210104_P01_WALL-PANEL-ASSY-SIDE-UPPER-RH_CAD (Autodesk Fusion 360 design; units mm, degrees)
description: WALL - PANEL ASSY - SIDE UPPER - RH | Vách phải - cụm tấm trên | P01 | position R2
part number: 210104
description: WALL - PANEL FRAME - SIDE UPPER - RH | Vách phải - khung trên | P01
part number: 211104
description: WALL - SKIN - SIDE UPPER - RH | Vách phải - tấm ốp alu trên | P01
part number: 211304
description: WALL - CAVITY FILL - SIDE UPPER - RH | Vách phải - bông PET trên | P01
part number: 211504
description: HARDWARE - STOP WASHER - Ø10.5 X Ø20 X 1.5 - AL | Long đen chặn nhôm | P01
part number: 831002
description: HARDWARE - RIVET NUT - M6 - SHEREX CAH3-610-4.2 | Tán rút M6 | P01
part number: 838003
Autodesk Fusion 360 part; units mm, degrees
(part 1 of 2)
ref_plane "WorkPlane1" through (0, 0, 1257.26) normal (0, 0, 1) x (1, 0, 0) in component "211104 WALL - PANEL FRAME - SIDE UPPER - RH"
sketch "SKETCH - RAIL - BOTTOM TUBE" plane through (0, 0, 1257.26) normal (0, 0, 1) x (1, 0, 0) in component "211104 WALL - PANEL FRAME - SIDE UPPER - RH"
  line L0 (1204, -642.74) -> (1244, -642.74)
  line L1 (1244, -642.74) -> (1244, 847)
  line L2 (1244, 847) -> (1204, 847)
  line L3 (1204, 847) -> (1204, -642.74)
  dimension "d167" = 40
  dimension "d168" = 1489.74
  dimension "d169" = 1204
  dimension "d170" = 642.74
  constraint horizontal L0
  constraint vertical L1
  constraint horizontal L2
  constraint vertical L3
  measures "d167" horizontal distance of L0.start L0.end
  measures "d168" vertical distance of L0.start L2.end
  measures "d169" horizontal distance of origin L0.start
  measures "d170" vertical distance of origin L0.start
extrude "EXTRUDE - RAIL - BOTTOM TUBE" add sketch "SKETCH - RAIL - BOTTOM TUBE" along normal blind 20 makes body 1 in component "211104 WALL - PANEL FRAME - SIDE UPPER - RH"
ref_plane "WorkPlane2" through (0, 0, 1258.46) normal (0, 0, 1) x (1, 0, 0) in component "211104 WALL - PANEL FRAME - SIDE UPPER - RH"
sketch "SKETCH - RAIL - BOTTOM BORE" plane through (0, 0, 1258.46) normal (0, 0, 1) x (1, 0, 0) in component "211104 WALL - PANEL FRAME - SIDE UPPER - RH"
  line L0 (1205.2, -642.74) -> (1242.8, -642.74)
  line L1 (1242.8, -642.74) -> (1242.8, 847)
  line L2 (1242.8, 847) -> (1205.2, 847)
  line L3 (1205.2, 847) -> (1205.2, -642.74)
  dimension "d175" = 37.6
  dimension "d176" = 1489.74
  dimension "d177" = 1205.2
  dimension "d178" = 642.74
  constraint horizontal L0
  constraint vertical L1
  constraint horizontal L2
  constraint vertical L3
  measures "d175" horizontal distance of L0.start L0.end
  measures "d176" vertical distance of L0.start L2.end
  measures "d177" horizontal distance of origin L0.start
  measures "d178" vertical distance of origin L0.start
extrude "CUT - RAIL - BOTTOM BORE" cut sketch "SKETCH - RAIL - BOTTOM BORE" along normal blind 17.6 bodies 1 in component "211104 WALL - PANEL FRAME - SIDE UPPER - RH"
ref_plane "WorkPlane3" through (0, 0, 2360) normal (0, 0, 1) x (1, 0, 0) in component "211104 WALL - PANEL FRAME - SIDE UPPER - RH"
sketch "SKETCH - RAIL - TOP TUBE" plane through (0, 0, 2360) normal (0, 0, 1) x (1, 0, 0) in component "211104 WALL - PANEL FRAME - SIDE UPPER - RH"
  line L0 (1204, -642.74) -> (1244, -642.74)
  line L1 (1244, -642.74) -> (1244, 847)
  line L2 (1244, 847) -> (1204, 847)
  line L3 (1204, 847) -> (1204, -642.74)
  dimension "d183" = 40
  dimension "d184" = 1489.74
  dimension "d185" = 1204
  dimension "d186" = 642.74
  constraint horizontal L0
  constraint vertical L1
  constraint horizontal L2
  constraint vertical L3
  measures "d183" horizontal distance of L0.start L0.end
  measures "d184" vertical distance of L0.start L2.end
  measures "d185" horizontal distance of origin L0.start
  measures "d186" vertical distance of origin L0.start
extrude "EXTRUDE - RAIL - TOP TUBE" add sketch "SKETCH - RAIL - TOP TUBE" along normal blind 40 separate body makes body 2 in component "211104 WALL - PANEL FRAME - SIDE UPPER - RH"
ref_plane "WorkPlane4" through (0, 0, 2361.2) normal (0, 0, 1) x (1, 0, 0) in component "211104 WALL - PANEL FRAME - SIDE UPPER - RH"
sketch "SKETCH - RAIL - TOP BORE" plane through (0, 0, 2361.2) normal (0, 0, 1) x (1, 0, 0) in component "211104 WALL - PANEL FRAME - SIDE UPPER - RH"
  line L0 (1205.2, -642.74) -> (1242.8, -642.74)
  line L1 (1242.8, -642.74) -> (1242.8, 847)
  line L2 (1242.8, 847) -> (1205.2, 847)
  line L3 (1205.2, 847) -> (1205.2, -642.74)
  dimension "d191" = 37.6
  dimension "d192" = 1489.74
  dimension "d193" = 1205.2
  dimension "d194" = 642.74
  constraint horizontal L0
  constraint vertical L1
  constraint horizontal L2
  constraint vertical L3
  measures "d191" horizontal distance of L0.start L0.end
  measures "d192" vertical distance of L0.start L2.end
  measures "d193" horizontal distance of origin L0.start
  measures "d194" vertical distance of origin L0.start
extrude "CUT - RAIL - TOP BORE" cut sketch "SKETCH - RAIL - TOP BORE" along normal blind 37.6 bodies 2 in component "211104 WALL - PANEL FRAME - SIDE UPPER - RH"
ref_plane "WorkPlane5" through (0, 0, 1277.26) normal (0, 0, 1) x (1, 0, 0) in component "211104 WALL - PANEL FRAME - SIDE UPPER - RH"
sketch "SKETCH - STILE - FRONT TUBE" plane through (0, 0, 1277.26) normal (0, 0, 1) x (1, 0, 0) in component "211104 WALL - PANEL FRAME - SIDE UPPER - RH"
  line L0 (1204, -642.74) -> (1244, -642.74)
  line L1 (1244, -642.74) -> (1244, -622.74)
  line L2 (1244, -622.74) -> (1204, -622.74)
  line L3 (1204, -622.74) -> (1204, -642.74)
  dimension "d199" = 40
  dimension "d200" = 20
  dimension "d201" = 1204
  dimension "d202" = 642.74
  constraint horizontal L0
  constraint vertical L1
  constraint horizontal L2
  constraint vertical L3
  measures "d199" horizontal distance of L0.start L0.end
  measures "d200" vertical distance of L0.start L2.end
  measures "d201" horizontal distance of origin L0.start
  measures "d202" vertical distance of origin L0.start
extrude "EXTRUDE - STILE - FRONT TUBE" add sketch "SKETCH - STILE - FRONT TUBE" along normal blind 1082.74 separate body makes body 3 in component "211104 WALL - PANEL FRAME - SIDE UPPER - RH"
ref_plane "WorkPlane6" through (0, 0, 1277.26) normal (0, 0, 1) x (1, 0, 0) in component "211104 WALL - PANEL FRAME - SIDE UPPER - RH"
sketch "SKETCH - STILE - FRONT BORE" plane through (0, 0, 1277.26) normal (0, 0, 1) x (1, 0, 0) in component "211104 WALL - PANEL FRAME - SIDE UPPER - RH"
  line L0 (1205.2, -641.54) -> (1242.8, -641.54)
  line L1 (1242.8, -641.54) -> (1242.8, -623.94)
  line L2 (1242.8, -623.94) -> (1205.2, -623.94)
  line L3 (1205.2, -623.94) -> (1205.2, -641.54)
  dimension "d207" = 37.6
  dimension "d208" = 17.6
  dimension "d209" = 1205.2
  dimension "d210" = 641.54
  constraint horizontal L0
  constraint vertical L1
  constraint horizontal L2
  constraint vertical L3
  measures "d207" horizontal distance of L0.start L0.end
  measures "d208" vertical distance of L0.start L2.end
  measures "d209" horizontal distance of origin L0.start
  measures "d210" vertical distance of origin L0.start
extrude "CUT - STILE - FRONT BORE" cut sketch "SKETCH - STILE - FRONT BORE" along normal blind 1082.74 bodies 3 in component "211104 WALL - PANEL FRAME - SIDE UPPER - RH"
ref_plane "WorkPlane7" through (0, 0, 1277.26) normal (0, 0, 1) x (1, 0, 0) in component "211104 WALL - PANEL FRAME - SIDE UPPER - RH"
sketch "SKETCH - STILE - BACK TUBE" plane through (0, 0, 1277.26) normal (0, 0, 1) x (1, 0, 0) in component "211104 WALL - PANEL FRAME - SIDE UPPER - RH"
  line L0 (1204, 807) -> (1244, 807)
  line L1 (1244, 807) -> (1244, 847)
  line L2 (1244, 847) -> (1204, 847)
  line L3 (1204, 847) -> (1204, 807)
  dimension "d215" = 40
  dimension "d216" = 40
  dimension "d217" = 1204
  dimension "d218" = 807
  constraint horizontal L0
  constraint vertical L1
  constraint horizontal L2
  constraint vertical L3
  measures "d215" horizontal distance of L0.start L0.end
  measures "d216" vertical distance of L0.start L2.end
  measures "d217" horizontal distance of origin L0.start
  measures "d218" vertical distance of origin L0.start
extrude "EXTRUDE - STILE - BACK TUBE" add sketch "SKETCH - STILE - BACK TUBE" along normal blind 1082.74 separate body makes body 4 in component "211104 WALL - PANEL FRAME - SIDE UPPER - RH"
ref_plane "WorkPlane8" through (0, 0, 1277.26) normal (0, 0, 1) x (1, 0, 0) in component "211104 WALL - PANEL FRAME - SIDE UPPER - RH"
sketch "SKETCH - STILE - BACK BORE" plane through (0, 0, 1277.26) normal (0, 0, 1) x (1, 0, 0) in component "211104 WALL - PANEL FRAME - SIDE UPPER - RH"
  line L0 (1205.2, 808.2) -> (1242.8, 808.2)
  line L1 (1242.8, 808.2) -> (1242.8, 845.8)
  line L2 (1242.8, 845.8) -> (1205.2, 845.8)
  line L3 (1205.2, 845.8) -> (1205.2, 808.2)
  dimension "d223" = 37.6
  dimension "d224" = 37.6
  dimension "d225" = 1205.2
  dimension "d226" = 808.2
  constraint horizontal L0
  constraint vertical L1
  constraint horizontal L2
  constraint vertical L3
  measures "d223" horizontal distance of L0.start L0.end
  measures "d224" vertical distance of L0.start L2.end
  measures "d225" horizontal distance of origin L0.start
  measures "d226" vertical distance of origin L0.start
extrude "CUT - STILE - BACK BORE" cut sketch "SKETCH - STILE - BACK BORE" along normal blind 1082.74 bodies 4 in component "211104 WALL - PANEL FRAME - SIDE UPPER - RH"
ref_plane "WorkPlane9" through (0, 0, 1277.26) normal (0, 0, 1) x (1, 0, 0) in component "211104 WALL - PANEL FRAME - SIDE UPPER - RH"
sketch "SKETCH - STILE - MID 1 TUBE" plane through (0, 0, 1277.26) normal (0, 0, 1) x (1, 0, 0) in component "211104 WALL - PANEL FRAME - SIDE UPPER - RH"
  line L0 (1204, -277.805) -> (1244, -277.805)
  line L1 (1244, -277.805) -> (1244, -257.805)
  line L2 (1244, -257.805) -> (1204, -257.805)
  line L3 (1204, -257.805) -> (1204, -277.805)
  dimension "d231" = 40
  dimension "d232" = 20
  dimension "d233" = 1204
  dimension "d234" = 277.805
  constraint horizontal L0
  constraint vertical L1
  constraint horizontal L2
  constraint vertical L3
  measures "d231" horizontal distance of L0.start L0.end
  measures "d232" vertical distance of L0.start L2.end
  measures "d233" horizontal distance of origin L0.start
  measures "d234" vertical distance of origin L0.start
extrude "EXTRUDE - STILE - MID 1 TUBE" add sketch "SKETCH - STILE - MID 1 TUBE" along normal blind 1082.74 separate body makes body 5 in component "211104 WALL - PANEL FRAME - SIDE UPPER - RH"
ref_plane "WorkPlane10" through (0, 0, 1277.26) normal (0, 0, 1) x (1, 0, 0) in component "211104 WALL - PANEL FRAME - SIDE UPPER - RH"
sketch "SKETCH - STILE - MID 1 BORE" plane through (0, 0, 1277.26) normal (0, 0, 1) x (1, 0, 0) in component "211104 WALL - PANEL FRAME - SIDE UPPER - RH"
  line L0 (1205, -276.805) -> (1243, -276.805)
  line L1 (1243, -276.805) -> (1243, -258.805)
  line L2 (1243, -258.805) -> (1205, -258.805)
  line L3 (1205, -258.805) -> (1205, -276.805)
  dimension "d239" = 38
  dimension "d240" = 18
  dimension "d241" = 1205
  dimension "d242" = 276.805
  constraint horizontal L0
  constraint vertical L1
  constraint horizontal L2
  constraint vertical L3
  measures "d239" horizontal distance of L0.start L0.end
  measures "d240" vertical distance of L0.start L2.end
  measures "d241" horizontal distance of origin L0.start
  measures "d242" vertical distance of origin L0.start
extrude "CUT - STILE - MID 1 BORE" cut sketch "SKETCH - STILE - MID 1 BORE" along normal blind 1082.74 bodies 5 in component "211104 WALL - PANEL FRAME - SIDE UPPER - RH"
pattern_linear "PATTERN - STILES - MID" count 3 spacing 364.935 along (0, 1, 0) of bodies 5 makes body 6 at (1230.6667, 107.13, 1999.0867) makes body 7 at (1230.6667, 472.065, 1999.0867) in component "211104 WALL - PANEL FRAME - SIDE UPPER - RH"
ref_plane "WorkPlane1" through (0, 0, 1257.26) normal (0, 0, 1) x (1, 0, 0) in component "211304 WALL - SKIN - SIDE UPPER - RH"
sketch "SKETCH - SKIN PLATE" plane through (0, 0, 1257.26) normal (0, 0, 1) x (1, 0, 0) in component "211304 WALL - SKIN - SIDE UPPER - RH"
  line L0 (1247, -642.74) -> (1250, -642.74)
  line L1 (1250, -642.74) -> (1250, 850)
  line L2 (1250, 850) -> (1247, 850)
  line L3 (1247, 850) -> (1247, -642.74)
  dimension "d251" = 3
  dimension "d252" = 1492.74
  dimension "d253" = 1247
  dimension "d254" = 642.74
  constraint horizontal L0
  constraint vertical L1
  constraint horizontal L2
  constraint vertical L3
  measures "d251" horizontal distance of L0.start L0.end
  measures "d252" vertical distance of L0.start L2.end
  measures "d253" horizontal distance of origin L0.start
  measures "d254" vertical distance of origin L0.start
extrude "EXTRUDE - SKIN PLATE" add sketch "SKETCH - SKIN PLATE" along normal blind 1142.74 separate body makes body 8 in component "211304 WALL - SKIN - SIDE UPPER - RH"
ref_plane "WorkPlane2" through (0, 0, 1257.26) normal (0, 0, 1) x (1, 0, 0) in component "211304 WALL - SKIN - SIDE UPPER - RH"
sketch "SKETCH - SKIN BACK RETURN" plane through (0, 0, 1257.26) normal (0, 0, 1) x (1, 0, 0) in component "211304 WALL - SKIN - SIDE UPPER - RH"
  line L0 (1204, 847) -> (1247, 847)
  line L1 (1247, 847) -> (1247, 850)
  line L2 (1247, 850) -> (1204, 850)
  line L3 (1204, 850) -> (1204, 847)
  dimension "d259" = 43
  dimension "d260" = 3
  dimension "d261" = 1204
  dimension "d262" = 847
  constraint horizontal L0
  constraint vertical L1
  constraint horizontal L2
  constraint vertical L3
  measures "d259" horizontal distance of L0.start L0.end
  measures "d260" vertical distance of L0.start L2.end
  measures "d261" horizontal distance of origin L0.start
  measures "d262" vertical distance of origin L0.start
extrude "JOIN - SKIN BACK RETURN" add sketch "SKETCH - SKIN BACK RETURN" along normal blind 1142.74 bodies 8 in component "211304 WALL - SKIN - SIDE UPPER - RH"
ref_plane "WorkPlane1" through (0, 0, 1277.26) normal (0, 0, 1) x (1, 0, 0) in component "211504 WALL - CAVITY FILL - SIDE UPPER - RH"
sketch "SKETCH - FILL BAY 1" plane through (0, 0, 1277.26) normal (0, 0, 1) x (1, 0, 0) in component "211504 WALL - CAVITY FILL - SIDE UPPER - RH"
  line L0 (1204, -622.74) -> (1244, -622.74)
  line L1 (1244, -622.74) -> (1244, -277.805)
  line L2 (1244, -277.805) -> (1204, -277.805)
  line L3 (1204, -277.805) -> (1204, -622.74)
  dimension "d267" = 40
  dimension "d268" = 344.935
  dimension "d269" = 1204
  dimension "d270" = 622.74
  constraint horizontal L0
  constraint vertical L1
  constraint horizontal L2
  constraint vertical L3
  measures "d267" horizontal distance of L0.start L0.end
  measures "d268" vertical distance of L0.start L2.end
  measures "d269" horizontal distance of origin L0.start
  measures "d270" vertical distance of origin L0.start
extrude "EXTRUDE - FILL BAY 1" add sketch "SKETCH - FILL BAY 1" along normal blind 1082.74 separate body makes body 9 in component "211504 WALL - CAVITY FILL - SIDE UPPER - RH"
pattern_linear "PATTERN - FILL BAYS" count 3 spacing 364.935 along (0, 1, 0) of bodies 9 makes body 10 at (1204, -27.8483, 1999.0867) makes body 11 at (1204, 337.0867, 1999.0867) in component "211504 WALL - CAVITY FILL - SIDE UPPER - RH"
ref_plane "WorkPlane2" through (0, 0, 1277.26) normal (0, 0, 1) x (1, 0, 0) in component "211504 WALL - CAVITY FILL - SIDE UPPER - RH"
sketch "SKETCH - FILL BAY LAST" plane through (0, 0, 1277.26) normal (0, 0, 1) x (1, 0, 0) in component "211504 WALL - CAVITY FILL - SIDE UPPER - RH"
  line L0 (1204, 472.065) -> (1244, 472.065)
  line L1 (1244, 472.065) -> (1244, 807)
  line L2 (1244, 807) -> (1204, 807)
  line L3 (1204, 807) -> (1204, 472.065)
  dimension "d279" = 40
  dimension "d280" = 334.935
  dimension "d281" = 1204
  dimension "d282" = 472.065
  constraint horizontal L0
  constraint vertical L1
  constraint horizontal L2
  constraint vertical L3
  measures "d279" horizontal distance of L0.start L0.end
  measures "d280" vertical distance of L0.start L2.end
  measures "d281" horizontal distance of origin L0.start
  measures "d282" vertical distance of origin L0.start
extrude "EXTRUDE - FILL BAY LAST" add sketch "SKETCH - FILL BAY LAST" along normal blind 1082.74 separate body makes body 12 in component "211504 WALL - CAVITY FILL - SIDE UPPER - RH"
ref_plane "WorkPlane3" through (0, 0, 1277.26) normal (0, 0, 1) x (1, 0, 0) in component "211504 WALL - CAVITY FILL - SIDE UPPER - RH"
sketch "SKETCH - FILL POCKET BOTTOM BOLT 1" plane through (0, 0, 1277.26) normal (0, 0, 1) x (1, 0, 0) in component "211504 WALL - CAVITY FILL - SIDE UPPER - RH"
  line L0 (1204, -452.74) -> (1244, -452.74)
  line L1 (1244, -452.74) -> (1244, -392.74)
  line L2 (1244, -392.74) -> (1204, -392.74)
  line L3 (1204, -392.74) -> (1204, -452.74)
  dimension "d287" = 40
  dimension "d288" = 60
  dimension "d289" = 1204
  dimension "d290" = 452.74
  constraint horizontal L0
  constraint vertical L1
  constraint horizontal L2
  constraint vertical L3
  measures "d287" horizontal distance of L0.start L0.end
  measures "d288" vertical distance of L0.start L2.end
  measures "d289" horizontal distance of origin L0.start
  measures "d290" vertical distance of origin L0.start
extrude "CUT - FILL POCKET BOTTOM BOLT 1" cut sketch "SKETCH - FILL POCKET BOTTOM BOLT 1" along normal blind 60 bodies 9 in component "211504 WALL - CAVITY FILL - SIDE UPPER - RH"
ref_plane "WorkPlane4" through (0, 0, 1277.26) normal (0, 0, 1) x (1, 0, 0) in component "211504 WALL - CAVITY FILL - SIDE UPPER - RH"
sketch "SKETCH - FILL POCKET BOTTOM BOLT 2" plane through (0, 0, 1277.26) normal (0, 0, 1) x (1, 0, 0) in component "211504 WALL - CAVITY FILL - SIDE UPPER - RH"
  line L0 (1204, -101.8267) -> (1244, -101.8267)
  line L1 (1244, -101.8267) -> (1244, -41.8267)
  line L2 (1244, -41.8267) -> (1204, -41.8267)
  line L3 (1204, -41.8267) -> (1204, -101.8267)
  dimension "d295" = 40
  dimension "d296" = 60
  dimension "d297" = 1204
  dimension "d298" = 101.8267
  constraint horizontal L0
  constraint vertical L1
  constraint horizontal L2
  constraint vertical L3
  measures "d295" horizontal distance of L0.start L0.end
  measures "d296" vertical distance of L0.start L2.end
  measures "d297" horizontal distance of origin L0.start
  measures "d298" vertical distance of origin L0.start
extrude "CUT - FILL POCKET BOTTOM BOLT 2" cut sketch "SKETCH - FILL POCKET BOTTOM BOLT 2" along normal blind 60 bodies 10 in component "211504 WALL - CAVITY FILL - SIDE UPPER - RH"
ref_plane "WorkPlane5" through (0, 0, 1277.26) normal (0, 0, 1) x (1, 0, 0) in component "211504 WALL - CAVITY FILL - SIDE UPPER - RH"
sketch "SKETCH - FILL POCKET BOTTOM BOLT 3" plane through (0, 0, 1277.26) normal (0, 0, 1) x (1, 0, 0) in component "211504 WALL - CAVITY FILL - SIDE UPPER - RH"
  line L0 (1204, 249.0867) -> (1244, 249.0867)
  line L1 (1244, 249.0867) -> (1244, 309.0867)
  line L2 (1244, 309.0867) -> (1204, 309.0867)
  line L3 (1204, 309.0867) -> (1204, 249.0867)
  dimension "d303" = 40
  dimension "d304" = 60
  dimension "d305" = 1204
  dimension "d306" = 249.0867
  constraint horizontal L0
  constraint vertical L1
  constraint horizontal L2
  constraint vertical L3
  measures "d303" horizontal distance of L0.start L0.end
  measures "d304" vertical distance of L0.start L2.end
  measures "d305" horizontal distance of origin L0.start
  measures "d306" vertical distance of origin L0.start
extrude "CUT - FILL POCKET BOTTOM BOLT 3" cut sketch "SKETCH - FILL POCKET BOTTOM BOLT 3" along normal blind 60 bodies 11 in component "211504 WALL - CAVITY FILL - SIDE UPPER - RH"
ref_plane "WorkPlane6" through (0, 0, 1277.26) normal (0, 0, 1) x (1, 0, 0) in component "211504 WALL - CAVITY FILL - SIDE UPPER - RH"
sketch "SKETCH - FILL POCKET BOTTOM BOLT 4" plane through (0, 0, 1277.26) normal (0, 0, 1) x (1, 0, 0) in component "211504 WALL - CAVITY FILL - SIDE UPPER - RH"
  line L0 (1204, 600) -> (1244, 600)
  line L1 (1244, 600) -> (1244, 660)
  line L2 (1244, 660) -> (1204, 660)
  line L3 (1204, 660) -> (1204, 600)
  dimension "d311" = 40
  dimension "d312" = 60
  dimension "d313" = 1204
  dimension "d314" = 600
  constraint horizontal L0
  constraint vertical L1
  constraint horizontal L2
  constraint vertical L3
  measures "d311" horizontal distance of L0.start L0.end
  measures "d312" vertical distance of L0.start L2.end
  measures "d313" horizontal distance of origin L0.start
  measures "d314" vertical distance of origin L0.start
extrude "CUT - FILL POCKET BOTTOM BOLT 4" cut sketch "SKETCH - FILL POCKET BOTTOM BOLT 4" along normal blind 60 bodies 12 in component "211504 WALL - CAVITY FILL - SIDE UPPER - RH"
ref_plane "WorkPlane7" through (0, 0, 1447.26) normal (0, 0, 1) x (1, 0, 0) in component "211504 WALL - CAVITY FILL - SIDE UPPER - RH"
sketch "SKETCH - FILL POCKET DECOR BOLT 1" plane through (0, 0, 1447.26) normal (0, 0, 1) x (1, 0, 0) in component "211504 WALL - CAVITY FILL - SIDE UPPER - RH"
  line L0 (1204, -622.74) -> (1244, -622.74)
  line L1 (1244, -622.74) -> (1244, -562.74)
  line L2 (1244, -562.74) -> (1204, -562.74)
  line L3 (1204, -562.74) -> (1204, -622.74)
  dimension "d319" = 40
  dimension "d320" = 60
  dimension "d321" = 1204
  dimension "d322" = 622.74
  constraint horizontal L0
  constraint vertical L1
  constraint horizontal L2
  constraint vertical L3
  measures "d319" horizontal distance of L0.start L0.end
  measures "d320" vertical distance of L0.start L2.end
  measures "d321" horizontal distance of origin L0.start
  measures "d322" vertical distance of origin L0.start
extrude "CUT - FILL POCKET DECOR BOLT 1" cut sketch "SKETCH - FILL POCKET DECOR BOLT 1" along normal blind 60 bodies 9 in component "211504 WALL - CAVITY FILL - SIDE UPPER - RH"
ref_plane "WorkPlane8" through (0, 0, 1798.63) normal (0, 0, 1) x (1, 0, 0) in component "211504 WALL - CAVITY FILL - SIDE UPPER - RH"
sketch "SKETCH - FILL POCKET DECOR BOLT 2" plane through (0, 0, 1798.63) normal (0, 0, 1) x (1, 0, 0) in component "211504 WALL - CAVITY FILL - SIDE UPPER - RH"
  line L0 (1204, -622.74) -> (1244, -622.74)
  line L1 (1244, -622.74) -> (1244, -562.74)
  line L2 (1244, -562.74) -> (1204, -562.74)
  line L3 (1204, -562.74) -> (1204, -622.74)
  dimension "d327" = 40
  dimension "d328" = 60
  dimension "d329" = 1204
  dimension "d330" = 622.74
  constraint horizontal L0
  constraint vertical L1
  constraint horizontal L2
  constraint vertical L3
  measures "d327" horizontal distance of L0.start L0.end
  measures "d328" vertical distance of L0.start L2.end
  measures "d329" horizontal distance of origin L0.start
  measures "d330" vertical distance of origin L0.start
extrude "CUT - FILL POCKET DECOR BOLT 2" cut sketch "SKETCH - FILL POCKET DECOR BOLT 2" along normal blind 60 bodies 9 in component "211504 WALL - CAVITY FILL - SIDE UPPER - RH"
ref_plane "WorkPlane9" through (0, 0, 2150) normal (0, 0, 1) x (1, 0, 0) in component "211504 WALL - CAVITY FILL - SIDE UPPER - RH"
sketch "SKETCH - FILL POCKET DECOR BOLT 3" plane through (0, 0, 2150) normal (0, 0, 1) x (1, 0, 0) in component "211504 WALL - CAVITY FILL - SIDE UPPER - RH"
  line L0 (1204, -622.74) -> (1244, -622.74)
  line L1 (1244, -622.74) -> (1244, -562.74)
  line L2 (1244, -562.74) -> (1204, -562.74)
  line L3 (1204, -562.74) -> (1204, -622.74)
  dimension "d335" = 40
  dimension "d336" = 60
  dimension "d337" = 1204
  dimension "d338" = 622.74
  constraint horizontal L0
  constraint vertical L1
  constraint horizontal L2
  constraint vertical L3
  measures "d335" horizontal distance of L0.start L0.end
  measures "d336" vertical distance of L0.start L2.end
  measures "d337" horizontal distance of origin L0.start
  measures "d338" vertical distance of origin L0.start
extrude "CUT - FILL POCKET DECOR BOLT 3" cut sketch "SKETCH - FILL POCKET DECOR BOLT 3" along normal blind 60 bodies 9 in component "211504 WALL - CAVITY FILL - SIDE UPPER - RH"
ref_plane "WorkPlane11" through (0, 0, 1257.26) normal (0, 0, 1) x (1, 0, 0) in component "211104 WALL - PANEL FRAME - SIDE UPPER - RH"
sketch "HOLE CENTRE - BOTTOM RAIL BOLT CLEARANCE 1" plane through (0, 0, 1257.26) normal (0, 0, 1) x (1, 0, 0) in component "211104 WALL - PANEL FRAME - SIDE UPPER - RH"
  point P0 (1224, -422.74)
  dimension "d343" = 1224
  dimension "d344" = 422.74
  measures "d343" horizontal distance of origin P0
  measures "d344" vertical distance of origin P0
hole "HOLE - BOTTOM RAIL BOLT CLEARANCE 1" at (1224, -422.74, 1257.26) direction (0, 0, 1) diameter 7 depth 1.2 tip angle 118 bodies 1 in component "211104 WALL - PANEL FRAME - SIDE UPPER - RH"
ref_plane "WorkPlane12" through (0, 0, 1277.26) normal (0, 0, 1) x (1, 0, 0) in component "211104 WALL - PANEL FRAME - SIDE UPPER - RH"
sketch "HOLE CENTRE - BOTTOM RAIL KEY ACCESS 1" plane through (0, 0, 1277.26) normal (0, 0, 1) x (1, 0, 0) in component "211104 WALL - PANEL FRAME - SIDE UPPER - RH"
  point P0 (1224, -422.74)
  dimension "d350" = 1224
  dimension "d351" = 422.74
  measures "d350" horizontal distance of origin P0
  measures "d351" vertical distance of origin P0
hole "HOLE - BOTTOM RAIL KEY ACCESS 1" at (1224, -422.74, 1277.26) direction (0, 0, -1) diameter 19 depth 1.2 tip angle 118 bodies 1 in component "211104 WALL - PANEL FRAME - SIDE UPPER - RH"
pattern_linear "PATTERN - BOTTOM RAIL BOLT HOLES" count 4 spacing 350.9133 along (0, 1, 0) of "HOLE - BOTTOM RAIL BOLT CLEARANCE 1", "HOLE - BOTTOM RAIL KEY ACCESS 1" in component "211104 WALL - PANEL FRAME - SIDE UPPER - RH"
ref_plane "WorkPlane13" through (0, 0, 1257.26) normal (0, 0, 1) x (1, 0, 0) in component "211104 WALL - PANEL FRAME - SIDE UPPER - RH"
sketch "HOLE CENTRE - BOTTOM RAIL SPIGOT ROUND" plane through (0, 0, 1257.26) normal (0, 0, 1) x (1, 0, 0) in component "211104 WALL - PANEL FRAME - SIDE UPPER - RH"
  point P0 (1224, -542.74)
  dimension "d361" = 1224
  dimension "d362" = 542.74
  measures "d361" horizontal distance of origin P0
  measures "d362" vertical distance of origin P0
hole "HOLE - BOTTOM RAIL SPIGOT ROUND" at (1224, -542.74, 1257.26) direction (0, 0, 1) diameter 8.5 depth 1.2 tip angle 118 bodies 1 in component "211104 WALL - PANEL FRAME - SIDE UPPER - RH"
ref_plane "WorkPlane14" through (0, 0, 1257.26) normal (0, 0, 1) x (1, 0, 0) in component "211104 WALL - PANEL FRAME - SIDE UPPER - RH"
sketch "SKETCH - BOTTOM RAIL SPIGOT SLOT" plane through (0, 0, 1257.26) normal (0, 0, 1) x (1, 0, 0) in component "211104 WALL - PANEL FRAME - SIDE UPPER - RH"
  line L0 (1221.25, 745.75) -> (1226.75, 745.75)
  line L1 (1226.75, 745.75) -> (1226.75, 754.25)
  line L2 (1226.75, 754.25) -> (1221.25, 754.25)
  line L3 (1221.25, 754.25) -> (1221.25, 745.75)
  dimension "d368" = 5.5
  dimension "d369" = 8.5
  dimension "d370" = 1221.25
  dimension "d371" = 745.75
  constraint horizontal L0
  constraint vertical L1
  constraint horizontal L2
  constraint vertical L3
  measures "d368" horizontal distance of L0.start L0.end
  measures "d369" vertical distance of L0.start L2.end
  measures "d370" horizontal distance of origin L0.start
  measures "d371" vertical distance of origin L0.start
extrude "CUT - BOTTOM RAIL SPIGOT SLOT" cut sketch "SKETCH - BOTTOM RAIL SPIGOT SLOT" along normal blind 1.2 bodies 1 in component "211104 WALL - PANEL FRAME - SIDE UPPER - RH"
ref_plane "WorkPlane15" through (0, 0, 1257.26) normal (0, 0, 1) x (1, 0, 0) in component "211104 WALL - PANEL FRAME - SIDE UPPER - RH"
sketch "HOLE CENTRE - BOTTOM RAIL SPIGOT SLOT END 1" plane through (0, 0, 1257.26) normal (0, 0, 1) x (1, 0, 0) in component "211104 WALL - PANEL FRAME - SIDE UPPER - RH"
  point P0 (1221.25, 750)
  dimension "d376" = 1221.25
  dimension "d377" = 750
  measures "d376" horizontal distance of origin P0
  measures "d377" vertical distance of origin P0
hole "HOLE - BOTTOM RAIL SPIGOT SLOT END 1" at (1221.25, 750, 1257.26) direction (0, 0, 1) diameter 8.5 depth 1.2 tip angle 118 bodies 1 in component "211104 WALL - PANEL FRAME - SIDE UPPER - RH"
ref_plane "WorkPlane16" through (0, 0, 1257.26) normal (0, 0, 1) x (1, 0, 0) in component "211104 WALL - PANEL FRAME - SIDE UPPER - RH"
sketch "HOLE CENTRE - BOTTOM RAIL SPIGOT SLOT END 2" plane through (0, 0, 1257.26) normal (0, 0, 1) x (1, 0, 0) in component "211104 WALL - PANEL FRAME - SIDE UPPER - RH"
  point P0 (1226.75, 750)
  dimension "d383" = 1226.75
  dimension "d384" = 750
  measures "d383" horizontal distance of origin P0
  measures "d384" vertical distance of origin P0
hole "HOLE - BOTTOM RAIL SPIGOT SLOT END 2" at (1226.75, 750, 1257.26) direction (0, 0, 1) diameter 8.5 depth 1.2 tip angle 118 bodies 1 in component "211104 WALL - PANEL FRAME - SIDE UPPER - RH"
ref_plane "WorkPlane17" through (1204, 0, 0) normal (1, 0, 0) x (0, 1, 0) in component "211104 WALL - PANEL FRAME - SIDE UPPER - RH"
sketch "HOLE CENTRE - TOP MEMBER CEILING RIVNUT 1" plane through (1204, 0, 0) normal (1, 0, 0) x (0, 0, -1) in component "211104 WALL - PANEL FRAME - SIDE UPPER - RH"
  point P0 (-2374, -425)
  dimension "d390" = 425
  dimension "d391" = 2374
  measures "d390" vertical distance of origin P0
  measures "d391" horizontal distance of origin P0
hole "HOLE - TOP MEMBER CEILING RIVNUT 1" at (1204, -425, 2374) direction (1, 0, 0) diameter 9.53 depth 1.2 tip angle 118 bodies 2 in component "211104 WALL - PANEL FRAME - SIDE UPPER - RH"
pattern_linear "PATTERN - TOP MEMBER CEILING RIVNUTS" count 4 spacing 351.6667 along (0, 1, 0) of "HOLE - TOP MEMBER CEILING RIVNUT 1" in component "211104 WALL - PANEL FRAME - SIDE UPPER - RH"
ref_plane "WorkPlane18" through (0, -642.74, 0) normal (0, 1, 0) x (0, 0, 1) in component "211104 WALL - PANEL FRAME - SIDE UPPER - RH"
sketch "HOLE CENTRE - FRONT STILE BOLT CLEARANCE 1" plane through (0, -642.74, 0) normal (0, 1, 0) x (1, 0, 0) in component "211104 WALL - PANEL FRAME - SIDE UPPER - RH"
  point P0 (1224, -1477.26)
  dimension "d401" = 1224
  dimension "d402" = 1477.26
  measures "d401" horizontal distance of origin P0
  measures "d402" vertical distance of origin P0
hole "HOLE - FRONT STILE BOLT CLEARANCE 1" at (1224, -642.74, 1477.26) direction (0, 1, 0) diameter 7 depth 1.2 tip angle 118 bodies 3 in component "211104 WALL - PANEL FRAME - SIDE UPPER - RH"
ref_plane "WorkPlane19" through (0, -622.74, 0) normal (0, 1, 0) x (0, 0, 1) in component "211104 WALL - PANEL FRAME - SIDE UPPER - RH"
sketch "HOLE CENTRE - FRONT STILE KEY ACCESS 1" plane through (0, -622.74, 0) normal (0, 1, 0) x (1, 0, 0) in component "211104 WALL - PANEL FRAME - SIDE UPPER - RH"
  point P0 (1224, -1477.26)
  dimension "d408" = 1224
  dimension "d409" = 1477.26
  measures "d408" horizontal distance of origin P0
  measures "d409" vertical distance of origin P0
hole "HOLE - FRONT STILE KEY ACCESS 1" at (1224, -622.74, 1477.26) direction (0, -1, 0) diameter 19 depth 1.2 tip angle 118 bodies 3 in component "211104 WALL - PANEL FRAME - SIDE UPPER - RH"
pattern_linear "PATTERN - FRONT STILE BOLT HOLES" count 3 spacing 351.37 along (0, 0, 1) of "HOLE - FRONT STILE BOLT CLEARANCE 1", "HOLE - FRONT STILE KEY ACCESS 1" in component "211104 WALL - PANEL FRAME - SIDE UPPER - RH"
ref_plane "WorkPlane20" through (1204, 0, 0) normal (1, 0, 0) x (0, 1, 0) in component "211104 WALL - PANEL FRAME - SIDE UPPER - RH"
sketch "HOLE CENTRE - BACK STILE CORNER RIVNUT 1" plane through (1204, 0, 0) normal (1, 0, 0) x (0, 0, -1) in component "211104 WALL - PANEL FRAME - SIDE UPPER - RH"
  point P0 (-1453.13, 824)
  dimension "d419" = 824
  dimension "d420" = 1453.13
  measures "d419" vertical distance of origin P0
  measures "d420" horizontal distance of origin P0
hole "HOLE - BACK STILE CORNER RIVNUT 1" at (1204, 824, 1453.13) direction (1, 0, 0) diameter 9.53 depth 1.2 tip angle 118 bodies 4 in component "211104 WALL - PANEL FRAME - SIDE UPPER - RH"
pattern_linear "PATTERN - BACK STILE CORNER RIVNUTS" count 3 spacing 339.305 along (0, 0, 1) of "HOLE - BACK STILE CORNER RIVNUT 1" in component "211104 WALL - PANEL FRAME - SIDE UPPER - RH"
ref_plane "WorkPlane1" through (1204, 0, 0) normal (1, 0, 0) x (0, 1, 0) in component "831002 HARDWARE - STOP WASHER - Ø10.5 X Ø20 X 1.5 - AL"
sketch "SKETCH - STOP WASHER TOP MEMBER CEILING" plane through (1204, 0, 0) normal (1, 0, 0) x (0, 0, -1) in component "831002 HARDWARE - STOP WASHER - Ø10.5 X Ø20 X 1.5 - AL"
  circle A0 centre (-2374, -425) radius 10
  circle A1 centre (-2374, -425) radius 5.25
  dimension "d430" = 425
  dimension "d431" = 2374
  dimension "d432" = 20
  dimension "d433" = 10.5
  measures "d430" vertical distance of origin A0.centre
  measures "d431" horizontal distance of origin A0.centre
  measures "d432" diameter of A0
  measures "d433" diameter of A1
extrude "EXTRUDE - STOP WASHER TOP MEMBER CEILING" add sketch "SKETCH - STOP WASHER TOP MEMBER CEILING" against normal blind 1.5 separate body makes body 13 in component "831002 HARDWARE - STOP WASHER - Ø10.5 X Ø20 X 1.5 - AL"
ref_plane "WorkPlane1" through (1202.5, 0, 0) normal (1, 0, 0) x (0, 1, 0) in component "838003 HARDWARE - RIVET NUT - M6 - SHEREX CAH3-610-4.2"
sketch "SKETCH - RIVNUT HEAD TOP MEMBER CEILING" plane through (1202.5, 0, 0) normal (1, 0, 0) x (0, 0, -1) in component "838003 HARDWARE - RIVET NUT - M6 - SHEREX CAH3-610-4.2"
  circle A0 centre (-2374, -425) radius 6.48
  circle A1 centre (-2374, -425) radius 3
  dimension "d440" = 425
  dimension "d441" = 2374
  dimension "d442" = 12.96
  dimension "d443" = 6
  measures "d440" vertical distance of origin A0.centre
  measures "d441" horizontal distance of origin A0.centre
  measures "d442" diameter of A0
  measures "d443" diameter of A1
extrude "EXTRUDE - RIVNUT HEAD TOP MEMBER CEILING" add sketch "SKETCH - RIVNUT HEAD TOP MEMBER CEILING" against normal blind 0.76 separate body makes body 14 in component "838003 HARDWARE - RIVET NUT - M6 - SHEREX CAH3-610-4.2"
ref_plane "WorkPlane2" through (1202.5, 0, 0) normal (1, 0, 0) x (0, 1, 0) in component "838003 HARDWARE - RIVET NUT - M6 - SHEREX CAH3-610-4.2"
sketch "SKETCH - RIVNUT BODY TOP MEMBER CEILING" plane through (1202.5, 0, 0) normal (1, 0, 0) x (0, 0, -1) in component "838003 HARDWARE - RIVET NUT - M6 - SHEREX CAH3-610-4.2"
  circle A0 centre (-2374, -425) radius 4.75
  circle A1 centre (-2374, -425) radius 3
  dimension "d450" = 425
  dimension "d451" = 2374
  dimension "d452" = 9.5
  dimension "d453" = 6
  measures "d450" vertical distance of origin A0.centre
  measures "d451" horizontal distance of origin A0.centre
  measures "d452" diameter of A0
  measures "d453" diameter of A1
extrude "EXTRUDE - RIVNUT BODY TOP MEMBER CEILING" add sketch "SKETCH - RIVNUT BODY TOP MEMBER CEILING" along normal blind 10.16 separate body makes body 15 in component "838003 HARDWARE - RIVET NUT - M6 - SHEREX CAH3-610-4.2"
combine "COMBINE - RIVNUT TOP MEMBER CEILING" operation add target body 14 tool bodies 15 in component "838003 HARDWARE - RIVET NUT - M6 - SHEREX CAH3-610-4.2"
pattern_linear "PATTERN - STOP WASHER - TOP MEMBER CEILING" count 4 spacing 351.6667 along (0, 1, 0) of bodies 13 makes body 16 at (1204, -68.2025, 2380.6436) makes body 17 at (1204, 283.4641, 2367.3564) makes body 18 at (1204, 624.8692, 2380.6436) in component "831002 HARDWARE - STOP WASHER - Ø10.5 X Ø20 X 1.5 - AL"
pattern_linear "PATTERN - RIVNUT - TOP MEMBER CEILING" count 4 spacing 351.6667 along (0, 1, 0) of bodies 14 makes body 19 at (1209.2733, -69.3432, 2371.4229) makes body 20 at (1209.2733, 282.3235, 2371.4229) makes body 21 at (1209.2733, 631.8451, 2369.623) in component "838003 HARDWARE - RIVET NUT - M6 - SHEREX CAH3-610-4.2"
ref_plane "WorkPlane2" through (1204, 0, 0) normal (1, 0, 0) x (0, 1, 0) in component "831002 HARDWARE - STOP WASHER - Ø10.5 X Ø20 X 1.5 - AL"
sketch "SKETCH - STOP WASHER BACK STILE CORNER" plane through (1204, 0, 0) normal (1, 0, 0) x (0, 0, -1) in component "831002 HARDWARE - STOP WASHER - Ø10.5 X Ø20 X 1.5 - AL"
  circle A0 centre (-1453.13, 824) radius 10
  circle A1 centre (-1453.13, 824) radius 5.25
  dimension "d466" = 824
  dimension "d467" = 1453.13
  dimension "d468" = 20
  dimension "d469" = 10.5
  measures "d466" vertical distance of origin A0.centre
  measures "d467" horizontal distance of origin A0.centre
  measures "d468" diameter of A0
  measures "d469" diameter of A1
extrude "EXTRUDE - STOP WASHER BACK STILE CORNER" add sketch "SKETCH - STOP WASHER BACK STILE CORNER" against normal blind 1.5 separate body makes body 22 in component "831002 HARDWARE - STOP WASHER - Ø10.5 X Ø20 X 1.5 - AL"
ref_plane "WorkPlane3" through (1202.5, 0, 0) normal (1, 0, 0) x (0, 1, 0) in component "838003 HARDWARE - RIVET NUT - M6 - SHEREX CAH3-610-4.2"
sketch "SKETCH - RIVNUT HEAD BACK STILE CORNER" plane through (1202.5, 0, 0) normal (1, 0, 0) x (0, 0, -1) in component "838003 HARDWARE - RIVET NUT - M6 - SHEREX CAH3-610-4.2"
  circle A0 centre (-1453.13, 824) radius 6.48
  circle A1 centre (-1453.13, 824) radius 3
  dimension "d476" = 824
  dimension "d477" = 1453.13
  dimension "d478" = 12.96
  dimension "d479" = 6
  measures "d476" vertical distance of origin A0.centre
  measures "d477" horizontal distance of origin A0.centre
  measures "d478" diameter of A0
  measures "d479" diameter of A1
extrude "EXTRUDE - RIVNUT HEAD BACK STILE CORNER" add sketch "SKETCH - RIVNUT HEAD BACK STILE CORNER" against normal blind 0.76 separate body makes body 23 in component "838003 HARDWARE - RIVET NUT - M6 - SHEREX CAH3-610-4.2"
ref_plane "WorkPlane4" through (1202.5, 0, 0) normal (1, 0, 0) x (0, 1, 0) in component "838003 HARDWARE - RIVET NUT - M6 - SHEREX CAH3-610-4.2"
sketch "SKETCH - RIVNUT BODY BACK STILE CORNER" plane through (1202.5, 0, 0) normal (1, 0, 0) x (0, 0, -1) in component "838003 HARDWARE - RIVET NUT - M6 - SHEREX CAH3-610-4.2"
  circle A0 centre (-1453.13, 824) radius 4.75
  circle A1 centre (-1453.13, 824) radius 3
  dimension "d486" = 824
  dimension "d487" = 1453.13
  dimension "d488" = 9.5
  dimension "d489" = 6
  measures "d486" vertical distance of origin A0.centre
  measures "d487" horizontal distance of origin A0.centre
  measures "d488" diameter of A0
  measures "d489" diameter of A1
extrude "EXTRUDE - RIVNUT BODY BACK STILE CORNER" add sketch "SKETCH - RIVNUT BODY BACK STILE CORNER" along normal blind 10.16 separate body makes body 24 in component "838003 HARDWARE - RIVET NUT - M6 - SHEREX CAH3-610-4.2"
combine "COMBINE - RIVNUT BACK STILE CORNER" operation add target body 23 tool bodies 24 in component "838003 HARDWARE - RIVET NUT - M6 - SHEREX CAH3-610-4.2"
pattern_linear "PATTERN - STOP WASHER - BACK STILE CORNER" count 3 spacing 339.305 along (0, 0, 1) of bodies 22 makes body 25 at (1204, 815.6811, 1793.5566) makes body 26 at (1204, 829.3353, 2125.2595) in component "831002 HARDWARE - STOP WASHER - Ø10.5 X Ø20 X 1.5 - AL"
pattern_linear "PATTERN - RIVNUT - BACK STILE CORNER" count 3 spacing 339.305 along (0, 0, 1) of bodies 23 makes body 27 at (1209.2733, 828.2269, 1790.268) makes body 28 at (1209.2733, 825.8451, 2127.363) in component "838003 HARDWARE - RIVET NUT - M6 - SHEREX CAH3-610-4.2"
component "211104 WALL - PANEL FRAME - SIDE UPPER - RH" placed x (1, 0, 0) y (0, 1, 0) z (0, 0, 1) at (0, 0, 0)
component "211304 WALL - SKIN - SIDE UPPER - RH" placed x (1, 0, 0) y (0, 1, 0) z (0, 0, 1) at (0, 0, 0)
component "211504 WALL - CAVITY FILL - SIDE UPPER - RH" placed x (1, 0, 0) y (0, 1, 0) z (0, 0, 1) at (0, 0, 0)
component "831002 HARDWARE - STOP WASHER - Ø10.5 X Ø20 X 1.5 - AL" placed x (1, 0, 0) y (0, 1, 0) z (0, 0, 1) at (0, 0, 0)
component "838003 HARDWARE - RIVET NUT - M6 - SHEREX CAH3-610-4.2" placed x (1, 0, 0) y (0, 1, 0) z (0, 0, 1) at (0, 0, 0)
equation "pod_w_Ref = 2500 mm" comment "DECIDED: D-01; conventions s4 (X = +-1250)"
equation "pod_d_Ref = 1700 mm" comment "DECIDED: D-01; conventions s4 (Y = +-850)"
equation "pod_h_Ref = 2400 mm" comment "DECIDED: D-21 (room floor to roof skin top)"
equation "glide_h_Ref = 10 mm" comment "ASSUMPTION: layout study inputs.py glide_h"
equation "band_h_Ref = 100 mm" comment "SOURCE: layout study B1 list B-BAND 100x40; inputs.py base_h"
equation "outer_t_Ref = skin_t_Ref + bond_t_Ref + frame_t_Ref" comment "DECIDED: PM ruling 2026-10-31: ACP 3 + bond line 3 + frame 40, walls and ceiling (was 43)"
equation "cav_gap_Ref = 4 mm" comment "DECIDED: D-16, D-42: the gap between the outer panel and the lining cassette in the wall and ceiling stack"
equation "cass_t_Ref = 34 mm" comment "SOURCE: layout study B1 final list L-CASS 34 (tray + 25 gap + felt 9)"
equation "stack_t_Ref = outer_t_Ref + cav_gap_Ref + cass_t_Ref" comment "CALCULATION: D-16, D-42 stack, walls and ceiling: outer panel + cavity gap + cassette (PM ruling 2026-10-31 on outer_t)"
equation "wall_depth_Ref = 1495 mm" comment "DECIDED: PM ruling pass C: side walls start at the decor back plate (Y -645), as v1 (1496)"
equation "lin_gap_Ref = 4 mm" comment "ASSUMPTION: PM ruling pass C: gap above the upper side linings so they stay floating (= the 4 mm stack gap)"
equation "seam_gap_Ref = 2.26 mm" comment "DECIDED: PM ruling 2026-10-31 (Mechanical Checker F-001, F-005): the Joints Engineer's 2.26 mm at all nine site seam types, set by a metal stop (1.5 stop washer + 0.76 rivnut head; joints register section 2.8)"
equation "wall_z0_Ref = glide_h_Ref + band_h_Ref" comment "CALCULATION: base band top: glides + band"
equation "panel_z0_Ref = wall_z0_Ref + seam_gap_Ref" comment "CALCULATION: walls stand one seam_gap above the band top (joints register 2.8, IF-01)"
equation "wall_h_Ref = pod_h_Ref - wall_z0_Ref" comment "CALCULATION: 2290 = layout study v2_model wall_h"
equation "side_h_Ref = ( wall_h_Ref - 2 * seam_gap_Ref ) / 2" comment "CALCULATION: D-23: 2 sheets per side wall; the gap on the band and the horizontal seam (joints register 2.8)"
equation "back_oh_Ref = pod_h_Ref - outer_t_Ref - seam_gap_Ref - panel_z0_Ref" comment "CALCULATION: PM ruling 2026-10-31 (pass D, F-004): the back outer frames run up to the ceiling frame (pod_h - outer_t), less the seam_gap under it, closing the slot at the back top edge"
equation "back_ph_Ref = ( back_oh_Ref - seam_gap_Ref ) / 2" comment "CALCULATION: D-23: 4 sheets on the back, two equal rows with one seam_gap between them (joints register 2.8); the lower back linings match the lower row, as on the side walls"
equation "n_base_bolt_Ref = 4" comment "DECIDED: PM ruling 2026-10-31, J-BASE-01: bolts per panel along the band, evenly spaced"
equation "skin_t_Ref = 3 mm" comment "DECIDED: ACP skin, walls and ceiling (D-16; PM ruling 2026-10-31 on outer_t)"
equation "bond_t_Ref = 3 mm" comment "DECIDED: bond line between the ACP and the frame (PM ruling 2026-10-31 on outer_t)"
equation "frame_t_Ref = 40 mm" comment "DECIDED: aluminium frame tube depth, walls and ceiling (PM ruling 2026-10-31 on outer_t)"
equation "bolt_edge_inset_Ref = 220 mm" comment "DECIDED: PM ruling 2026-10-31: on every bolted edge the end bolts sit this far in from each panel end (the FRAME end, where the bolts go), the rest evenly spaced"
equation "spigot_inset_Ref = 100 mm" comment "DECIDED: PM ruling 2026-10-31: locating spigots this far in from each panel end (round hole at one end, slot at the other)"
equation "ceil_bolt_z_Ref = pod_h_Ref - outer_t_Ref + frame_t_Ref / 2" comment "DECIDED: PM ruling 2026-10-31, J-CEIL-01 wall to ceiling: the bolt line on the ceiling frame's centre (Z 2374)"
equation "pod_w = pod_w_Ref" comment "LINKED: pod_w_Ref, derived from 100000_P04_POD-SKELETON_CAD v4 (skeleton is the single source)"
equation "pod_d = pod_d_Ref" comment "LINKED: pod_d_Ref, derived from 100000_P04_POD-SKELETON_CAD v4 (skeleton is the single source)"
equation "pod_h = pod_h_Ref" comment "LINKED: pod_h_Ref, derived from 100000_P04_POD-SKELETON_CAD v4 (skeleton is the single source)"
equation "wall_depth = wall_depth_Ref" comment "LINKED: wall_depth_Ref, derived from 100000_P04_POD-SKELETON_CAD v4 (skeleton is the single source)"
equation "wall_z0 = wall_z0_Ref" comment "LINKED: wall_z0_Ref, derived from 100000_P04_POD-SKELETON_CAD v4 (skeleton is the single source)"
equation "panel_z0 = panel_z0_Ref" comment "LINKED: panel_z0_Ref, derived from 100000_P04_POD-SKELETON_CAD v4 (skeleton is the single source)"
equation "side_h = side_h_Ref" comment "LINKED: side_h_Ref, derived from 100000_P04_POD-SKELETON_CAD v4 (skeleton is the single source)"
equation "back_ph = back_ph_Ref" comment "LINKED: back_ph_Ref, derived from 100000_P04_POD-SKELETON_CAD v4 (skeleton is the single source)"
equation "stack_t = stack_t_Ref" comment "LINKED: stack_t_Ref, derived from 100000_P04_POD-SKELETON_CAD v4 (skeleton is the single source)"
equation "outer_t = outer_t_Ref" comment "LINKED: outer_t_Ref, derived from 100000_P04_POD-SKELETON_CAD v4 (skeleton is the single source)"
equation "cass_t = cass_t_Ref" comment "LINKED: cass_t_Ref, derived from 100000_P04_POD-SKELETON_CAD v4 (skeleton is the single source)"
equation "lin_gap = lin_gap_Ref" comment "LINKED: lin_gap_Ref, derived from 100000_P04_POD-SKELETON_CAD v4 (skeleton is the single source)"
equation "seam_gap = seam_gap_Ref" comment "LINKED: seam_gap_Ref, derived from 100000_P04_POD-SKELETON_CAD v4 (skeleton is the single source)"
equation "skin_t = skin_t_Ref" comment "LINKED: skin_t_Ref, derived from 100000_P04_POD-SKELETON_CAD v4 (skeleton is the single source)"
equation "bond_t = bond_t_Ref" comment "LINKED: bond_t_Ref, derived from 100000_P04_POD-SKELETON_CAD v4 (skeleton is the single source)"
equation "bolt_edge_inset = bolt_edge_inset_Ref" comment "LINKED: bolt_edge_inset_Ref, derived from 100000_P04_POD-SKELETON_CAD v4 (skeleton is the single source)"
equation "spigot_inset = spigot_inset_Ref" comment "LINKED: spigot_inset_Ref, derived from 100000_P04_POD-SKELETON_CAD v4 (skeleton is the single source)"
equation "n_base_bolt = n_base_bolt_Ref" comment "LINKED: n_base_bolt_Ref, derived from 100000_P04_POD-SKELETON_CAD v4 (skeleton is the single source)"
equation "ceil_bolt_z = ceil_bolt_z_Ref" comment "LINKED: ceil_bolt_z_Ref, derived from 100000_P04_POD-SKELETON_CAD v4 (skeleton is the single source)"
equation "tube_w = 20 mm" comment "CONFIRMED: D-34, D-54: aluminium tube 20 x 40 x 1.2; the 20 mm face carries the skin, so the 40 mm runs through the wall (outer_t = ACP 3 + frame 40). The joint register may turn it for the bond width (HOLD)"
equation "tube_d = outer_t - skin_t - bond_t" comment "CALCULATION: frame depth = outer panel 46 - skin 3 - bond 3 = 40 (D-34)"
equation "tube_t = 1.2 mm" comment "CONFIRMED: D-34, D-54, D-85: perimeter members (rails, front and back stiles) keep the 1.2 mm wall; they carry the rivnuts (grip check passed)"
equation "stud_t = 1.0 mm" comment "CONFIRMED: D-85 (weight): intermediate studs at a 1.0 mm wall; they carry no rivnut, only the skin's bond line"
equation "stile_pitch_max = 400 mm" comment "CONFIRMED: D-16, D-34: members 400 mm apart or less, to keep the ACP flat"
equation "pnl_len = wall_depth - seam_gap" comment "CALCULATION: D-49 depth 1495 less the 2.26 gap at the decor back plate (PM ruling on F-008): 1492.74"
equation "pnl_h = pod_h - ( panel_z0 + side_h + seam_gap )" comment "CALCULATION: lower: skeleton side_h (2 sheets per side wall, D-23); upper: from one seam gap above the lower row to the roof datum pod_h, as the skeleton's envelope (equal to side_h at P04 values)"
equation "skin_ret = outer_t - skin_t" comment "ASSUMPTION: back return of the side skin: covers the frame's back end at the corner, where the side skin covers the back panel's edge (D-55; sample drawing D04). V-groove and fold per the ACP maker (HOLD H16)"
equation "skin_setback = 0 mm" comment "ASSUMPTION: skin edge set back from the frame's top and bottom edges: 0, so the outside reveal equals the 2.26 seam gap (D-23: crisp, aligned reveals; joints register 2.8 leaves the setback to the WALL drawing)"
equation "frm_len = pnl_len - skin_t" comment "CALCULATION: the frame stops at the inside of the skin's back return"
equation "frm_h = pnl_h" comment "ASSUMPTION: the frame fills the skeleton envelope height; seam and base gasket gaps are set by the joint register (HOLD)"
equation "corner_w = 40 mm" comment "CONFIRMED: the side panel's back member is 40 x 40 x 1.2 (PM ruling on the joints register, item 3, 2026-10-31; register F2, FR-06): the back corner joint needs a 37+ mm overlap for the rivnut and the bolt"
equation "stile_n_mid = ceil(( frm_len - tube_w / 2 - corner_w / 2 ) / stile_pitch_max) - 1" comment "CALCULATION: intermediate stiles so that no stile pitch (centre to centre) exceeds stile_pitch_max"
equation "stile_pitch = ( frm_len - tube_w / 2 - corner_w / 2 ) / ( stile_n_mid + 1 )" comment "CALCULATION: equal stile pitch, centre to centre, from the front stile to the 40 mm back stile"
equation "top_h = corner_w" comment "CONFIRMED: top member height: 20 on a lower panel; 40 x 40 on an upper panel, where the ceiling bolts in (PM ruling R-J3, joints register FR-06)"
equation "stile_len = frm_h - tube_w - top_h" comment "CALCULATION: stiles fit between the full-length rails (butt joints)"
equation "ceil_bolt_dz = pod_h - ceil_bolt_z" comment "CALCULATION: J-CEIL-01 side bolts on the ceiling frame tube's centre: the skeleton's ceil_bolt_z, Z 2374 on P04 (joints register R-J15, FR-07)"
equation "fill_t = tube_d" comment "CALCULATION: 40 mm PET fill fills the frame depth (D-34; layout study 40 mm)"
equation "bolt_d = 7 mm" comment "CONFIRMED: PM ruling on F-009: bolt holes 7.0 (0.51 float), position tolerance 0.4 (+-0.2) from the spigot hole, CNC or drill jig (joints register FR-02)"
equation "access_d = 19 mm" comment "CALCULATION: register FR-03: passes the 18 mm head washer (ISO 7093-1, R-J10), the M6 head and the 5 mm key; holds the grommet retainer (H-02)"
equation "bolt_line_y = pod_d / 2 - skin_t - bond_t - tube_d / 2" comment "CONFIRMED: J-WALL-02 bolt line on the back panel's tube centre, Y 824 (joints register R-J15, FR-07)"
equation "rivnut_d = 9.53 mm" comment "SOURCE: Sherex CAH3-610-4.2 hole 9.53 +0.10 (HW-SEL A5; register H-03)"